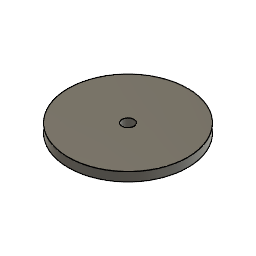
SolidDisc_100radps (Autodesk Fusion 360 design; units mm, degrees)
part number: 2026-08-28-14-11-31-386
Autodesk Fusion 360 part; units mm, degrees
sketch "Sketch1" plane through (0, 0, 0) normal (0, 1, 0) x (1, 0, 0)
  circle A0 centre (0, 0) radius 100
  dimension "d1" = 200
  constraint coincident A0.centre origin
  measures "d1" diameter of A0
extrude "Extrude1" add sketch "Sketch1" along normal blind 15
hole "Hole2" at (0, 15, 0) direction (0, -1, 0) diameter 20 end through all
